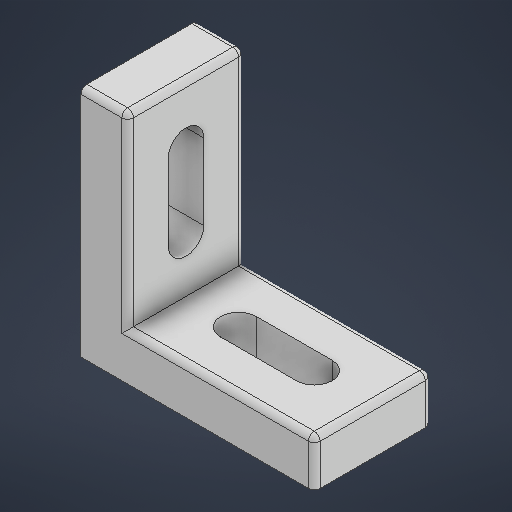
# Autodesk Inventor part: Befestigungswinkel 40 x 40 mit Langloch, schwarz
Saved by Autodesk Inventor 2027.1 (Build 311270010, 270A)
## iProperties
Created: 2026-10-20
Part Number: Befestigungswinkel 40 x 40 mit Langloch, schwarz
Material: Generic
Document SubType Name: Modeling
Designer: nicol
Density: 1 g/cm^3
Appearance: Default
Author: nicol
Autodesk Inventor part; units mm, degrees
ref_plane "YZ Plane" through (0, 0, 0) normal (1, 0, 0) x (0, 1, 0)
ref_plane "XZ Plane" through (0, 0, 0) normal (0, 1, 0) x (-1, 0, 0)
ref_plane "XY Plane" through (0, 0, 0) normal (0, 0, 1) x (1, 0, 0)
sketch "Sketch1" plane through (0, 0, 0) normal (0, 1, 0) x (-1, 0, 0)
  line L0 (0, 10) -> (-40, 10)
  line L1 (-40, 10) -> (-40, -10)
  line L2 (-40, -10) -> (0, -10)
  line L3 (0, -10) -> (0, 10)
  point P0 (0, 0)
  dimension "d0" = 0
  dimension "d1" = 20
  dimension "d2" = 40
  dimension "d3" = 10
  constraints: 8 end point, 2 parallel, 1 horizontal, 1 perpendicular
  measures "d0" distance from line of L3 point (0, 0)
  measures "d1" distance between parallel lines of L0 L2
  measures "d2" distance between parallel lines of L1 L3
  measures "d3" distance from line of point (0, 0) L2
extrude "Extrusion1" add sketch "Sketch1" along normal blind 8
sketch "Sketch2" plane through (0, 8, 0) normal (0, 1, 0) x (1, 0, 0)
  line L0 (0, -10) -> (8, -10)
  line L1 (8, -10) -> (8, 10)
  line L2 (8, 10) -> (0, 10)
  line L3 (0, 10) -> (0, -10)
  line L4 (0, 10) -> (0, -10) projected
  line L5 (0, -10) -> (40, -10) projected
  line L6 (40, 10) -> (0, 10) projected
  point P0 (0, 0)
  dimension "d6" = 0
  dimension "d7" = 0
  dimension "d8" = 0
  dimension "d9" = 8
  constraints: 8 end point, 2 parallel, 1 horizontal, 1 perpendicular
  measures "d6" distance between parallel lines of L4 L3
  measures "d7" distance between parallel lines of L5 L0
  measures "d8" distance between parallel lines of L6 L2
  measures "d9" distance between parallel lines of L3 L1
extrude "Extrusion2" add sketch "Sketch2" along normal blind 32
sketch "Sketch3" plane through (0, 8, 0) normal (0, 1, 0) x (1, 0, 0)
  line L0 (17, 3.05) -> (30, 3.05)
  line L1 (33.05, 0) -> (33.05, 0)
  line L2 (30, -3.05) -> (17, -3.05)
  line L3 (13.95, 0) -> (13.95, 0)
  line L4 (40, -10) -> (40, 10) projected
  arc A0 (17, 3.05) -> (13.95, 0) centre (17, 0) ccw
  arc A1 (13.95, 0) -> (17, -3.05) centre (17, 0) ccw
  arc A2 (30, -3.05) -> (33.05, 0) centre (30, 0) ccw
  arc A3 (33.05, 0) -> (30, 3.05) centre (30, 0) ccw
  line L5 (8, -10) -> (40, -10) projected
  point P0 (0, 0)
  point P1 (13.95, 0)
  dimension "d12" = 6.1
  dimension "d16" = 13
  dimension "d17" = 0
  dimension "d18" = 10
  dimension "d29" = 10
  constraints: 8 end point, 8 point on circle, 8 tangent, 4 centre point, 3 equal radius, 2 parallel, 1 horizontal, 1 perpendicular
  measures "d12" distance between parallel lines of L2 L0
  measures "d16" distance of A3.centre A0.centre
  measures "d17" distance of A1.centre A0.centre
  measures "d18" distance from line of L4 A2.centre
  measures "d29" distance from line of L5 A2.centre
extrude "Extrusion3" cut sketch "Sketch3" against normal up to surface (8 mm away)
sketch "Sketch4" plane through (8, 8, 10) normal (1, 0, 0) x (0, 0, -1)
  line L0 (10, 25.05) -> (10, 25.05)
  line L1 (6.95, 22) -> (6.95, 9)
  line L2 (10, 5.95) -> (10, 5.95)
  line L3 (13.05, 9) -> (13.05, 22)
  arc A0 (13.05, 22) -> (10, 25.05) centre (10, 22) ccw
  arc A1 (10, 25.05) -> (6.95, 22) centre (10, 22) ccw
  arc A2 (6.95, 9) -> (10, 5.95) centre (10, 9) ccw
  arc A3 (10, 5.95) -> (13.05, 9) centre (10, 9) ccw
  line L4 (0, 32) -> (20, 32) projected
  line L5 (20, 0) -> (20, 32) projected
  point P0 (10, -8)
  point P1 (10, 5.95)
  point P2 (10, 25.05)
  dimension "d22" = 0
  dimension "d23" = 10
  dimension "d24" = 6.1
  dimension "d25" = 10
  dimension "d26" = 13
  constraints: 8 end point, 8 point on circle, 8 tangent, 4 centre point, 3 equal radius, 2 parallel, 1 horizontal, 1 perpendicular
  measures "d22" distance of A1.centre A0.centre
  measures "d23" distance from line of L4 A0.centre
  measures "d24" distance between parallel lines of L1 L3
  measures "d25" distance from line of L5 A0.centre
  measures "d26" distance of A0.centre A2.centre
extrude "Extrusion4" cut sketch "Sketch4" against normal up to surface (8 mm away)
fillet "Fillet1" radius 1 10 edges at (4, 40, 10) (8, 40, 0) (4, 40, -10) (8, 24, -10) (8, 24, 10) (24, 8, 10) (24, 8, -10) (40, 8, 0) (40, 4, 10) (40, 4, -10)
body "Solid1"
